Autodesk Fusion 360 part; units mm, degrees
(part 2 of 4)
  line L951 (102.344, 60.9328) -> (103.145, 60.9328)
  line L952 (103.145, 60.9328) -> (103.145, 64.0334)
  line L953 (103.145, 64.0334) -> (102.344, 64.0334)
  line L954 (102.344, 64.0334) -> (102.344, 69.8334)
  line L955 (102.344, 69.8334) -> (103.145, 69.8334)
  line L956 (103.145, 69.8334) -> (103.145, 72.9326)
  line L957 (103.145, 72.9326) -> (102.344, 72.9326)
  line L958 (102.344, 72.9326) -> (102.344, 73.9331)
  line L959 (102.344, 73.9331) -> (88.3447, 73.9331)
  line L960 (107.395, 73.9331) -> (107.395, 72.9326)
  line L961 (107.395, 72.9326) -> (106.594, 72.9326)
  line L962 (106.594, 72.9326) -> (106.594, 69.8334)
  line L963 (106.594, 69.8334) -> (107.395, 69.8334)
  line L964 (107.395, 69.8334) -> (107.395, 64.0334)
  line L965 (107.395, 64.0334) -> (106.594, 64.0334)
  line L966 (106.594, 64.0334) -> (106.594, 60.9328)
  line L967 (106.594, 60.9328) -> (107.395, 60.9328)
  line L968 (107.395, 60.9328) -> (107.395, 59.9338)
  line L969 (107.395, 59.9338) -> (121.394, 59.9338)
  line L970 (121.394, 59.9338) -> (121.394, 60.9328)
  line L971 (121.394, 60.9328) -> (122.195, 60.9328)
  line L972 (122.195, 60.9328) -> (122.195, 64.0334)
  line L973 (122.195, 64.0334) -> (121.394, 64.0334)
  line L974 (121.394, 64.0334) -> (121.394, 69.8334)
  line L975 (121.394, 69.8334) -> (122.195, 69.8334)
  line L976 (122.195, 69.8334) -> (122.195, 72.9326)
  line L977 (122.195, 72.9326) -> (121.394, 72.9326)
  line L978 (121.394, 72.9326) -> (121.394, 73.9331)
  line L979 (121.394, 73.9331) -> (107.395, 73.9331)
  line L980 (126.445, 73.9331) -> (126.445, 72.9326)
  line L981 (126.445, 72.9326) -> (125.644, 72.9326)
  line L982 (125.644, 72.9326) -> (125.644, 69.8334)
  line L983 (125.644, 69.8334) -> (126.445, 69.8334)
  line L984 (126.445, 69.8334) -> (126.445, 64.0334)
  line L985 (126.445, 64.0334) -> (125.644, 64.0334)
  line L986 (125.644, 64.0334) -> (125.644, 60.9328)
  line L987 (125.644, 60.9328) -> (126.445, 60.9328)
  line L988 (126.445, 60.9328) -> (126.445, 59.9338)
  line L989 (126.445, 59.9338) -> (140.444, 59.9338)
  line L990 (140.444, 59.9338) -> (140.444, 60.9328)
  line L991 (140.444, 60.9328) -> (141.245, 60.9328)
  line L992 (141.245, 60.9328) -> (141.245, 64.0334)
  line L993 (141.245, 64.0334) -> (140.444, 64.0334)
  line L994 (140.444, 64.0334) -> (140.444, 69.8334)
  line L995 (140.444, 69.8334) -> (141.245, 69.8334)
  line L996 (141.245, 69.8334) -> (141.245, 72.9326)
  line L997 (141.245, 72.9326) -> (140.444, 72.9326)
  line L998 (140.444, 72.9326) -> (140.444, 73.9331)
  line L999 (140.444, 73.9331) -> (126.445, 73.9331)
  line L1000 (145.495, 73.9331) -> (145.495, 72.9326)
  line L1001 (145.495, 72.9326) -> (144.694, 72.9326)
  line L1002 (144.694, 72.9326) -> (144.694, 69.8334)
  line L1003 (144.694, 69.8334) -> (145.495, 69.8334)
  line L1004 (145.495, 69.8334) -> (145.495, 64.0334)
  line L1005 (145.495, 64.0334) -> (144.694, 64.0334)
  line L1006 (144.694, 64.0334) -> (144.694, 60.9328)
  line L1007 (144.694, 60.9328) -> (145.495, 60.9328)
  line L1008 (145.495, 60.9328) -> (145.495, 59.9338)
  line L1009 (145.495, 59.9338) -> (159.494, 59.9338)
  line L1010 (159.494, 59.9338) -> (159.494, 60.9328)
  line L1011 (159.494, 60.9328) -> (160.295, 60.9328)
  line L1012 (160.295, 60.9328) -> (160.295, 64.0334)
  line L1013 (160.295, 64.0334) -> (159.494, 64.0334)
  line L1014 (159.494, 64.0334) -> (159.494, 69.8334)
  line L1015 (159.494, 69.8334) -> (160.295, 69.8334)
  line L1016 (160.295, 69.8334) -> (160.295, 72.9326)
  line L1017 (160.295, 72.9326) -> (159.494, 72.9326)
  line L1018 (159.494, 72.9326) -> (159.494, 73.9331)
  line L1019 (159.494, 73.9331) -> (145.495, 73.9331)
  line L1020 (164.545, 73.9331) -> (164.545, 72.9326)
  line L1021 (164.545, 72.9326) -> (163.744, 72.9326)
  line L1022 (163.744, 72.9326) -> (163.744, 69.8334)
  line L1023 (163.744, 69.8334) -> (164.545, 69.8334)
  line L1024 (164.545, 69.8334) -> (164.545, 64.0334)
  line L1025 (164.545, 64.0334) -> (163.744, 64.0334)
  line L1026 (163.744, 64.0334) -> (163.744, 60.9328)
  line L1027 (163.744, 60.9328) -> (164.545, 60.9328)
  line L1028 (164.545, 60.9328) -> (164.545, 59.9338)
  line L1029 (164.545, 59.9338) -> (178.544, 59.9338)
  line L1030 (178.544, 59.9338) -> (178.544, 60.9328)
  line L1031 (178.544, 60.9328) -> (179.345, 60.9328)
  line L1032 (179.345, 60.9328) -> (179.345, 64.0334)
  line L1033 (179.345, 64.0334) -> (178.544, 64.0334)
  line L1034 (178.544, 64.0334) -> (178.544, 69.8334)
  line L1035 (178.544, 69.8334) -> (179.345, 69.8334)
  line L1036 (179.345, 69.8334) -> (179.345, 72.9326)
  line L1037 (179.345, 72.9326) -> (178.544, 72.9326)
  line L1038 (178.544, 72.9326) -> (178.544, 73.9331)
  line L1039 (178.544, 73.9331) -> (164.545, 73.9331)
  line L1040 (183.595, 73.9331) -> (183.595, 72.9326)
  line L1041 (183.595, 72.9326) -> (182.794, 72.9326)
  line L1042 (182.794, 72.9326) -> (182.794, 69.8334)
  line L1043 (182.794, 69.8334) -> (183.595, 69.8334)
  line L1044 (183.595, 69.8334) -> (183.595, 64.0334)
  line L1045 (183.595, 64.0334) -> (182.794, 64.0334)
  line L1046 (182.794, 64.0334) -> (182.794, 60.9328)
  line L1047 (182.794, 60.9328) -> (183.595, 60.9328)
  line L1048 (183.595, 60.9328) -> (183.595, 59.9338)
  line L1049 (183.595, 59.9338) -> (197.594, 59.9338)
  line L1050 (197.594, 59.9338) -> (197.594, 60.9328)
  line L1051 (197.594, 60.9328) -> (198.395, 60.9328)
  line L1052 (198.395, 60.9328) -> (198.395, 64.0334)
  line L1053 (198.395, 64.0334) -> (197.594, 64.0334)
  line L1054 (197.594, 64.0334) -> (197.594, 69.8334)
  line L1055 (197.594, 69.8334) -> (198.395, 69.8334)
  line L1056 (198.395, 69.8334) -> (198.395, 72.9326)
  line L1057 (198.395, 72.9326) -> (197.594, 72.9326)
  line L1058 (197.594, 72.9326) -> (197.594, 73.9331)
  line L1059 (197.594, 73.9331) -> (183.595, 73.9331)
  line L1060 (202.645, 73.9331) -> (202.645, 72.9326)
  line L1061 (202.645, 72.9326) -> (201.844, 72.9326)
  line L1062 (201.844, 72.9326) -> (201.844, 69.8334)
  line L1063 (201.844, 69.8334) -> (202.645, 69.8334)
  line L1064 (202.645, 69.8334) -> (202.645, 64.0334)
  line L1065 (202.645, 64.0334) -> (201.844, 64.0334)
  line L1066 (201.844, 64.0334) -> (201.844, 60.9328)
  line L1067 (201.844, 60.9328) -> (202.645, 60.9328)
  line L1068 (202.645, 60.9328) -> (202.645, 59.9338)
  line L1069 (202.645, 59.9338) -> (216.644, 59.9338)
  line L1070 (216.644, 59.9338) -> (216.644, 60.9328)
  line L1071 (216.644, 60.9328) -> (217.445, 60.9328)
  line L1072 (217.445, 60.9328) -> (217.445, 64.0334)
  line L1073 (217.445, 64.0334) -> (216.644, 64.0334)
  line L1074 (216.644, 64.0334) -> (216.644, 69.8334)
  line L1075 (216.644, 69.8334) -> (217.445, 69.8334)
  line L1076 (217.445, 69.8334) -> (217.445, 72.9326)
  line L1077 (217.445, 72.9326) -> (216.644, 72.9326)
  line L1078 (216.644, 72.9326) -> (216.644, 73.9331)
  line L1079 (216.644, 73.9331) -> (202.645, 73.9331)
  line L1080 (221.695, 73.9331) -> (221.695, 72.9326)
  line L1081 (221.695, 72.9326) -> (220.894, 72.9326)
  line L1082 (220.894, 72.9326) -> (220.894, 69.8334)
  line L1083 (220.894, 69.8334) -> (221.695, 69.8334)
  line L1084 (221.695, 69.8334) -> (221.695, 64.0334)
  line L1085 (221.695, 64.0334) -> (220.894, 64.0334)
  line L1086 (220.894, 64.0334) -> (220.894, 60.9328)
  line L1087 (220.894, 60.9328) -> (221.695, 60.9328)
  line L1088 (221.695, 60.9328) -> (221.695, 59.9338)
  line L1089 (221.695, 59.9338) -> (235.694, 59.9338)
  line L1090 (235.694, 59.9338) -> (235.694, 60.9328)
  line L1091 (235.694, 60.9328) -> (236.495, 60.9328)
  line L1092 (236.495, 60.9328) -> (236.495, 64.0334)
  line L1093 (236.495, 64.0334) -> (235.694, 64.0334)
  line L1094 (235.694, 64.0334) -> (235.694, 69.8334)
  line L1095 (235.694, 69.8334) -> (236.495, 69.8334)
  line L1096 (236.495, 69.8334) -> (236.495, 72.9326)
  line L1097 (236.495, 72.9326) -> (235.694, 72.9326)
  line L1098 (235.694, 72.9326) -> (235.694, 73.9331)
  line L1099 (235.694, 73.9331) -> (221.695, 73.9331)
  line L1100 (240.745, 73.9331) -> (240.745, 72.9326)
  line L1101 (240.745, 72.9326) -> (239.944, 72.9326)
  line L1102 (239.944, 72.9326) -> (239.944, 69.8334)
  line L1103 (239.944, 69.8334) -> (240.745, 69.8334)
  line L1104 (240.745, 69.8334) -> (240.745, 64.0334)
  line L1105 (240.745, 64.0334) -> (239.944, 64.0334)
  line L1106 (239.944, 64.0334) -> (239.944, 60.9328)
  line L1107 (239.944, 60.9328) -> (240.745, 60.9328)
  line L1108 (240.745, 60.9328) -> (240.745, 59.9338)
  line L1109 (240.745, 59.9338) -> (254.744, 59.9338)
  line L1110 (254.744, 59.9338) -> (254.744, 60.9328)
  line L1111 (254.744, 60.9328) -> (255.545, 60.9328)
  line L1112 (255.545, 60.9328) -> (255.545, 64.0334)
  line L1113 (255.545, 64.0334) -> (254.744, 64.0334)
  line L1114 (254.744, 64.0334) -> (254.744, 69.8334)
  line L1115 (254.744, 69.8334) -> (255.545, 69.8334)
  line L1116 (255.545, 69.8334) -> (255.545, 72.9326)
  line L1117 (255.545, 72.9326) -> (254.744, 72.9326)
  line L1118 (254.744, 72.9326) -> (254.744, 73.9331)
  line L1119 (254.744, 73.9331) -> (240.745, 73.9331)
  line L1120 (264.557, 73.9331) -> (264.557, 72.9326)
  line L1121 (264.557, 72.9326) -> (263.756, 72.9326)
  line L1122 (263.756, 72.9326) -> (263.756, 69.8334)
  line L1123 (263.756, 69.8334) -> (264.557, 69.8334)
  line L1124 (264.557, 69.8334) -> (264.557, 64.0334)
  line L1125 (264.557, 64.0334) -> (263.756, 64.0334)
  line L1126 (263.756, 64.0334) -> (263.756, 60.9328)
  line L1127 (263.756, 60.9328) -> (264.557, 60.9328)
  line L1128 (264.557, 60.9328) -> (264.557, 59.9338)
  line L1129 (264.557, 59.9338) -> (278.557, 59.9338)
  line L1130 (278.557, 59.9338) -> (278.557, 60.9328)
  line L1131 (278.557, 60.9328) -> (279.356, 60.9328)
  line L1132 (279.356, 60.9328) -> (279.356, 64.0334)
  line L1133 (279.356, 64.0334) -> (278.557, 64.0334)
  line L1134 (278.557, 64.0334) -> (278.557, 69.8334)
  line L1135 (278.557, 69.8334) -> (279.356, 69.8334)
  line L1136 (279.356, 69.8334) -> (279.356, 72.9326)
  line L1137 (279.356, 72.9326) -> (278.557, 72.9326)
  line L1138 (278.557, 72.9326) -> (278.557, 73.9331)
  line L1139 (278.557, 73.9331) -> (264.557, 73.9331)
  line L1140 (288.37, 73.9331) -> (288.37, 72.9326)
  line L1141 (288.37, 72.9326) -> (287.569, 72.9326)
  line L1142 (287.569, 72.9326) -> (287.569, 69.8334)
  line L1143 (287.569, 69.8334) -> (288.37, 69.8334)
  line L1144 (288.37, 69.8334) -> (288.37, 64.0334)
  line L1145 (288.37, 64.0334) -> (287.569, 64.0334)
  line L1146 (287.569, 64.0334) -> (287.569, 60.9328)
  line L1147 (287.569, 60.9328) -> (288.37, 60.9328)
  line L1148 (288.37, 60.9328) -> (288.37, 59.9338)
  line L1149 (288.37, 59.9338) -> (302.369, 59.9338)
  line L1150 (302.369, 59.9338) -> (302.369, 60.9328)
  line L1151 (302.369, 60.9328) -> (303.17, 60.9328)
  line L1152 (303.17, 60.9328) -> (303.17, 64.0334)
  line L1153 (303.17, 64.0334) -> (302.369, 64.0334)
  line L1154 (302.369, 64.0334) -> (302.369, 69.8334)
  line L1155 (302.369, 69.8334) -> (303.17, 69.8334)
  line L1156 (303.17, 69.8334) -> (303.17, 72.9326)
  line L1157 (303.17, 72.9326) -> (302.369, 72.9326)
  line L1158 (302.369, 72.9326) -> (302.369, 73.9331)
  line L1159 (302.369, 73.9331) -> (288.37, 73.9331)
  line L1160 (259.795, 92.9831) -> (259.795, 91.9826)
  line L1161 (259.795, 91.9826) -> (258.994, 91.9826)
  line L1162 (258.994, 91.9826) -> (258.994, 88.8834)
  line L1163 (258.994, 88.8834) -> (259.795, 88.8834)
  line L1164 (259.795, 88.8834) -> (259.795, 88.2826)
  line L1165 (259.795, 88.2826) -> (258.269, 88.2826)
  line L1166 (258.269, 88.2826) -> (258.269, 91.5127)
  line L1167 (258.269, 91.5127) -> (251.52, 91.5127)
  line L1168 (251.52, 91.5127) -> (251.52, 88.2826)
  line L1169 (251.52, 88.2826) -> (250.694, 88.2826)
  line L1170 (250.694, 88.2826) -> (250.694, 85.4837)
  line L1171 (250.694, 85.4837) -> (251.52, 85.4837)
  line L1172 (251.52, 85.4837) -> (251.52, 79.2138)
  line L1173 (251.52, 79.2138) -> (253.243, 79.2138)
  line L1174 (253.243, 79.2138) -> (253.243, 78.0136)
  line L1175 (253.243, 78.0136) -> (256.544, 78.0136)
  line L1176 (256.544, 78.0136) -> (256.544, 79.2138)
  line L1177 (256.544, 79.2138) -> (258.269, 79.2138)
  line L1178 (258.269, 79.2138) -> (258.269, 83.6828)
  line L1179 (258.269, 83.6828) -> (259.795, 83.6828)
  line L1180 (259.795, 83.6828) -> (259.795, 83.0834)
  line L1181 (259.795, 83.0834) -> (258.994, 83.0834)
  line L1182 (258.994, 83.0834) -> (258.994, 79.9828)
  line L1183 (258.994, 79.9828) -> (259.795, 79.9828)
  line L1184 (259.795, 79.9828) -> (259.795, 78.9838)
  line L1185 (259.795, 78.9838) -> (273.794, 78.9838)
  line L1186 (273.794, 78.9838) -> (273.794, 79.9828)
  line L1187 (273.794, 79.9828) -> (274.595, 79.9828)
  line L1188 (274.595, 79.9828) -> (274.595, 83.0834)
  line L1189 (274.595, 83.0834) -> (273.794, 83.0834)
  line L1190 (273.794, 83.0834) -> (273.794, 83.6828)
  line L1191 (273.794, 83.6828) -> (275.32, 83.6828)
  line L1192 (275.32, 83.6828) -> (275.32, 79.2138)
  line L1193 (275.32, 79.2138) -> (277.045, 79.2138)
  line L1194 (277.045, 79.2138) -> (277.045, 78.0136)
  line L1195 (277.045, 78.0136) -> (280.344, 78.0136)
  line L1196 (280.344, 78.0136) -> (280.344, 79.2138)
  line L1197 (280.344, 79.2138) -> (282.069, 79.2138)
  line L1198 (282.069, 79.2138) -> (282.069, 85.4837)
  line L1199 (282.069, 85.4837) -> (282.895, 85.4837)
  line L1200 (282.895, 85.4837) -> (282.895, 88.2826)
  line L1201 (282.895, 88.2826) -> (282.069, 88.2826)
  line L1202 (282.069, 88.2826) -> (282.069, 91.5127)
  line L1203 (282.069, 91.5127) -> (275.32, 91.5127)
  line L1204 (275.32, 91.5127) -> (275.32, 88.2826)
  line L1205 (275.32, 88.2826) -> (273.794, 88.2826)
  line L1206 (273.794, 88.2826) -> (273.794, 88.8834)
  line L1207 (273.794, 88.8834) -> (274.595, 88.8834)
  line L1208 (274.595, 88.8834) -> (274.595, 91.9826)
  line L1209 (274.595, 91.9826) -> (273.794, 91.9826)
  line L1210 (273.794, 91.9826) -> (273.794, 92.9831)
  line L1211 (273.794, 92.9831) -> (259.795, 92.9831)
  line L1212 (2.6197, 92.9831) -> (2.6197, 91.9826)
  line L1213 (2.6197, 91.9826) -> (1.819, 91.9826)
  line L1214 (1.819, 91.9826) -> (1.819, 88.8834)
  line L1215 (1.819, 88.8834) -> (2.6197, 88.8834)
  line L1216 (2.6197, 88.8834) -> (2.6197, 83.0834)
  line L1217 (2.6197, 83.0834) -> (1.819, 83.0834)
  line L1218 (1.819, 83.0834) -> (1.819, 79.9828)
  line L1219 (1.819, 79.9828) -> (2.6197, 79.9828)
  line L1220 (2.6197, 79.9828) -> (2.6197, 78.9838)
  line L1221 (2.6197, 78.9838) -> (16.6192, 78.9838)
  line L1222 (16.6192, 78.9838) -> (16.6192, 79.9828)
  line L1223 (16.6192, 79.9828) -> (17.4198, 79.9828)
  line L1224 (17.4198, 79.9828) -> (17.4198, 83.0834)
  line L1225 (17.4198, 83.0834) -> (16.6192, 83.0834)
  line L1226 (16.6192, 83.0834) -> (16.6192, 88.8834)
  line L1227 (16.6192, 88.8834) -> (17.4198, 88.8834)
  line L1228 (17.4198, 88.8834) -> (17.4198, 91.9826)
  line L1229 (17.4198, 91.9826) -> (16.6192, 91.9826)
  line L1230 (16.6192, 91.9826) -> (16.6192, 92.9831)
  line L1231 (16.6192, 92.9831) -> (2.6196, 92.9831)
  line L1232 (21.6697, 92.9831) -> (21.6697, 91.9826)
  line L1233 (21.6697, 91.9826) -> (20.869, 91.9826)
  line L1234 (20.869, 91.9826) -> (20.869, 88.8834)
  line L1235 (20.869, 88.8834) -> (21.6697, 88.8834)
  line L1236 (21.6697, 88.8834) -> (21.6697, 83.0834)
  line L1237 (21.6697, 83.0834) -> (20.869, 83.0834)
  line L1238 (20.869, 83.0834) -> (20.869, 79.9828)
  line L1239 (20.869, 79.9828) -> (21.6697, 79.9828)
  line L1240 (21.6697, 79.9828) -> (21.6697, 78.9838)
  line L1241 (21.6697, 78.9838) -> (35.669, 78.9838)
  line L1242 (35.669, 78.9838) -> (35.669, 79.9828)
  line L1243 (35.669, 79.9828) -> (36.4698, 79.9828)
  line L1244 (36.4698, 79.9828) -> (36.4698, 83.0834)
  line L1245 (36.4698, 83.0834) -> (35.669, 83.0834)
  line L1246 (35.669, 83.0834) -> (35.669, 88.8834)
  line L1247 (35.669, 88.8834) -> (36.4698, 88.8834)
  line L1248 (36.4698, 88.8834) -> (36.4698, 91.9826)
  line L1249 (36.4698, 91.9826) -> (35.669, 91.9826)
  line L1250 (35.669, 91.9826) -> (35.669, 92.9831)
  line L1251 (35.669, 92.9831) -> (21.6697, 92.9831)
  line L1252 (40.7197, 92.9831) -> (40.7197, 91.9826)
  line L1253 (40.7197, 91.9826) -> (39.9189, 91.9826)
  line L1254 (39.9189, 91.9826) -> (39.9189, 88.8834)
  line L1255 (39.9189, 88.8834) -> (40.7197, 88.8834)
  line L1256 (40.7197, 88.8834) -> (40.7197, 83.0834)
  line L1257 (40.7197, 83.0834) -> (39.9189, 83.0834)
  line L1258 (39.9189, 83.0834) -> (39.9189, 79.9828)
  line L1259 (39.9189, 79.9828) -> (40.7197, 79.9828)
  line L1260 (40.7197, 79.9828) -> (40.7197, 78.9838)
  line L1261 (40.7197, 78.9838) -> (54.719, 78.9838)
  line L1262 (54.719, 78.9838) -> (54.719, 79.9828)
  line L1263 (54.719, 79.9828) -> (55.5198, 79.9828)
  line L1264 (55.5198, 79.9828) -> (55.5198, 83.0834)
  line L1265 (55.5198, 83.0834) -> (54.719, 83.0834)
  line L1266 (54.719, 83.0834) -> (54.719, 88.8834)
  line L1267 (54.719, 88.8834) -> (55.5198, 88.8834)
  line L1268 (55.5198, 88.8834) -> (55.5198, 91.9826)
  line L1269 (55.5198, 91.9826) -> (54.719, 91.9826)
  line L1270 (54.719, 91.9826) -> (54.719, 92.9831)
  line L1271 (54.719, 92.9831) -> (40.7197, 92.9831)
  line L1272 (59.7697, 92.9831) -> (59.7697, 91.9826)
  line L1273 (59.7697, 91.9826) -> (58.9689, 91.9826)
  line L1274 (58.9689, 91.9826) -> (58.9689, 88.8834)
  line L1275 (58.9689, 88.8834) -> (59.7697, 88.8834)
  line L1276 (59.7697, 88.8834) -> (59.7697, 83.0834)
  line L1277 (59.7697, 83.0834) -> (58.9689, 83.0834)
  line L1278 (58.9689, 83.0834) -> (58.9689, 79.9828)
  line L1279 (58.9689, 79.9828) -> (59.7697, 79.9828)
  line L1280 (59.7697, 79.9828) -> (59.7697, 78.9838)
  line L1281 (59.7697, 78.9838) -> (73.769, 78.9838)
  line L1282 (73.769, 78.9838) -> (73.769, 79.9828)
  line L1283 (73.769, 79.9828) -> (74.5698, 79.9828)
  line L1284 (74.5698, 79.9828) -> (74.5698, 83.0834)
  line L1285 (74.5698, 83.0834) -> (73.769, 83.0834)
  line L1286 (73.769, 83.0834) -> (73.769, 88.8834)
  line L1287 (73.769, 88.8834) -> (74.5698, 88.8834)
  line L1288 (74.5698, 88.8834) -> (74.5698, 91.9826)
  line L1289 (74.5698, 91.9826) -> (73.769, 91.9826)
  line L1290 (73.769, 91.9826) -> (73.769, 92.9831)
  line L1291 (73.769, 92.9831) -> (59.7697, 92.9831)
  line L1292 (78.8197, 92.9831) -> (78.8197, 91.9826)
  line L1293 (78.8197, 91.9826) -> (78.0189, 91.9826)
  line L1294 (78.0189, 91.9826) -> (78.0189, 88.8834)
  line L1295 (78.0189, 88.8834) -> (78.8197, 88.8834)
  line L1296 (78.8197, 88.8834) -> (78.8197, 83.0834)
  line L1297 (78.8197, 83.0834) -> (78.0189, 83.0834)
  line L1298 (78.0189, 83.0834) -> (78.0189, 79.9828)
  line L1299 (78.0189, 79.9828) -> (78.8197, 79.9828)
  line L1300 (78.8197, 79.9828) -> (78.8197, 78.9838)
  line L1301 (78.8197, 78.9838) -> (92.819, 78.9838)
  line L1302 (92.819, 78.9838) -> (92.819, 79.9828)
  line L1303 (92.819, 79.9828) -> (93.6184, 79.9828)
  line L1304 (93.6184, 79.9828) -> (93.6184, 83.0834)
  line L1305 (93.6184, 83.0834) -> (92.819, 83.0834)
  line L1306 (92.819, 83.0834) -> (92.819, 88.8834)
  line L1307 (92.819, 88.8834) -> (93.6184, 88.8834)
  line L1308 (93.6184, 88.8834) -> (93.6184, 91.9826)
  line L1309 (93.6184, 91.9826) -> (92.819, 91.9826)
  line L1310 (92.819, 91.9826) -> (92.819, 92.9831)
  line L1311 (92.819, 92.9831) -> (78.8197, 92.9831)
  line L1312 (97.8683, 92.9831) -> (97.8683, 91.9826)
  line L1313 (97.8683, 91.9826) -> (97.0689, 91.9826)
  line L1314 (97.0689, 91.9826) -> (97.0689, 88.8834)
  line L1315 (97.0689, 88.8834) -> (97.8683, 88.8834)
  line L1316 (97.8683, 88.8834) -> (97.8683, 83.0834)
  line L1317 (97.8683, 83.0834) -> (97.0689, 83.0834)
  line L1318 (97.0689, 83.0834) -> (97.0689, 79.9828)
  line L1319 (97.0689, 79.9828) -> (97.8683, 79.9828)
  line L1320 (97.8683, 79.9828) -> (97.8683, 78.9838)
  line L1321 (97.8683, 78.9838) -> (111.869, 78.9838)
  line L1322 (111.869, 78.9838) -> (111.869, 79.9828)
  line L1323 (111.869, 79.9828) -> (112.668, 79.9828)
  line L1324 (112.668, 79.9828) -> (112.668, 83.0834)
  line L1325 (112.668, 83.0834) -> (111.869, 83.0834)
  line L1326 (111.869, 83.0834) -> (111.869, 88.8834)
  line L1327 (111.869, 88.8834) -> (112.668, 88.8834)
  line L1328 (112.668, 88.8834) -> (112.668, 91.9826)
  line L1329 (112.668, 91.9826) -> (111.869, 91.9826)
  line L1330 (111.869, 91.9826) -> (111.869, 92.9831)
  line L1331 (111.869, 92.9831) -> (97.8683, 92.9831)
  line L1332 (116.918, 92.9831) -> (116.918, 91.9826)
  line L1333 (116.918, 91.9826) -> (116.119, 91.9826)
  line L1334 (116.119, 91.9826) -> (116.119, 88.8834)
  line L1335 (116.119, 88.8834) -> (116.918, 88.8834)
  line L1336 (116.918, 88.8834) -> (116.918, 83.0834)
  line L1337 (116.918, 83.0834) -> (116.119, 83.0834)
  line L1338 (116.119, 83.0834) -> (116.119, 79.9828)
  line L1339 (116.119, 79.9828) -> (116.918, 79.9828)
  line L1340 (116.918, 79.9828) -> (116.918, 78.9838)
  line L1341 (116.918, 78.9838) -> (130.919, 78.9838)
  line L1342 (130.919, 78.9838) -> (130.919, 79.9828)
  line L1343 (130.919, 79.9828) -> (131.72, 79.9828)
  line L1344 (131.72, 79.9828) -> (131.72, 83.0834)
  line L1345 (131.72, 83.0834) -> (130.919, 83.0834)
  line L1346 (130.919, 83.0834) -> (130.919, 88.8834)
  line L1347 (130.919, 88.8834) -> (131.72, 88.8834)
  line L1348 (131.72, 88.8834) -> (131.72, 91.9826)
  line L1349 (131.72, 91.9826) -> (130.919, 91.9826)
  line L1350 (130.919, 91.9826) -> (130.919, 92.9831)
  line L1351 (130.919, 92.9831) -> (116.918, 92.9831)
  line L1352 (135.97, 92.9831) -> (135.97, 91.9826)
  line L1353 (135.97, 91.9826) -> (135.169, 91.9826)
  line L1354 (135.169, 91.9826) -> (135.169, 88.8834)
  line L1355 (135.169, 88.8834) -> (135.97, 88.8834)
  line L1356 (135.97, 88.8834) -> (135.97, 83.0834)
  line L1357 (135.97, 83.0834) -> (135.169, 83.0834)
  line L1358 (135.169, 83.0834) -> (135.169, 79.9828)
  line L1359 (135.169, 79.9828) -> (135.97, 79.9828)
  line L1360 (135.97, 79.9828) -> (135.97, 78.9838)
  line L1361 (135.97, 78.9838) -> (149.969, 78.9838)
  line L1362 (149.969, 78.9838) -> (149.969, 79.9828)
  line L1363 (149.969, 79.9828) -> (150.77, 79.9828)
  line L1364 (150.77, 79.9828) -> (150.77, 83.0834)
  line L1365 (150.77, 83.0834) -> (149.969, 83.0834)
  line L1366 (149.969, 83.0834) -> (149.969, 88.8834)
  line L1367 (149.969, 88.8834) -> (150.77, 88.8834)
  line L1368 (150.77, 88.8834) -> (150.77, 91.9826)
  line L1369 (150.77, 91.9826) -> (149.969, 91.9826)
  line L1370 (149.969, 91.9826) -> (149.969, 92.9831)
  line L1371 (149.969, 92.9831) -> (135.97, 92.9831)
  line L1372 (155.02, 92.9831) -> (155.02, 91.9826)
  line L1373 (155.02, 91.9826) -> (154.219, 91.9826)
  line L1374 (154.219, 91.9826) -> (154.219, 88.8834)
  line L1375 (154.219, 88.8834) -> (155.02, 88.8834)
  line L1376 (155.02, 88.8834) -> (155.02, 83.0834)
  line L1377 (155.02, 83.0834) -> (154.219, 83.0834)
  line L1378 (154.219, 83.0834) -> (154.219, 79.9828)
  line L1379 (154.219, 79.9828) -> (155.02, 79.9828)
  line L1380 (155.02, 79.9828) -> (155.02, 78.9838)
  line L1381 (155.02, 78.9838) -> (169.019, 78.9838)
  line L1382 (169.019, 78.9838) -> (169.019, 79.9828)
  line L1383 (169.019, 79.9828) -> (169.82, 79.9828)
  line L1384 (169.82, 79.9828) -> (169.82, 83.0834)
  line L1385 (169.82, 83.0834) -> (169.019, 83.0834)
  line L1386 (169.019, 83.0834) -> (169.019, 88.8834)
  line L1387 (169.019, 88.8834) -> (169.82, 88.8834)
  line L1388 (169.82, 88.8834) -> (169.82, 91.9826)
  line L1389 (169.82, 91.9826) -> (169.019, 91.9826)
  line L1390 (169.019, 91.9826) -> (169.019, 92.9831)
  line L1391 (169.019, 92.9831) -> (155.02, 92.9831)
  line L1392 (174.07, 92.9831) -> (174.07, 91.9826)
  line L1393 (174.07, 91.9826) -> (173.269, 91.9826)
  line L1394 (173.269, 91.9826) -> (173.269, 88.8834)
  line L1395 (173.269, 88.8834) -> (174.07, 88.8834)
  line L1396 (174.07, 88.8834) -> (174.07, 83.0834)
  line L1397 (174.07, 83.0834) -> (173.269, 83.0834)
  line L1398 (173.269, 83.0834) -> (173.269, 79.9828)
  line L1399 (173.269, 79.9828) -> (174.07, 79.9828)
  line L1400 (174.07, 79.9828) -> (174.07, 78.9838)
  line L1401 (174.07, 78.9838) -> (188.069, 78.9838)
  line L1402 (188.069, 78.9838) -> (188.069, 79.9828)
  line L1403 (188.069, 79.9828) -> (188.87, 79.9828)
  line L1404 (188.87, 79.9828) -> (188.87, 83.0834)
  line L1405 (188.87, 83.0834) -> (188.069, 83.0834)
  line L1406 (188.069, 83.0834) -> (188.069, 88.8834)
  line L1407 (188.069, 88.8834) -> (188.87, 88.8834)
  line L1408 (188.87, 88.8834) -> (188.87, 91.9826)
  line L1409 (188.87, 91.9826) -> (188.069, 91.9826)
  line L1410 (188.069, 91.9826) -> (188.069, 92.9831)
  line L1411 (188.069, 92.9831) -> (174.07, 92.9831)
  line L1412 (193.12, 92.9831) -> (193.12, 91.9826)
  line L1413 (193.12, 91.9826) -> (192.319, 91.9826)
  line L1414 (192.319, 91.9826) -> (192.319, 88.8834)
  line L1415 (192.319, 88.8834) -> (193.12, 88.8834)
  line L1416 (193.12, 88.8834) -> (193.12, 83.0834)
  line L1417 (193.12, 83.0834) -> (192.319, 83.0834)
  line L1418 (192.319, 83.0834) -> (192.319, 79.9828)
  line L1419 (192.319, 79.9828) -> (193.12, 79.9828)
  line L1420 (193.12, 79.9828) -> (193.12, 78.9838)
  line L1421 (193.12, 78.9838) -> (207.119, 78.9838)
  line L1422 (207.119, 78.9838) -> (207.119, 79.9828)
  line L1423 (207.119, 79.9828) -> (207.92, 79.9828)
  line L1424 (207.92, 79.9828) -> (207.92, 83.0834)
  line L1425 (207.92, 83.0834) -> (207.119, 83.0834)
  line L1426 (207.119, 83.0834) -> (207.119, 88.8834)
  line L1427 (207.119, 88.8834) -> (207.92, 88.8834)
  line L1428 (207.92, 88.8834) -> (207.92, 91.9826)
  line L1429 (207.92, 91.9826) -> (207.119, 91.9826)
  line L1430 (207.119, 91.9826) -> (207.119, 92.9831)
  line L1431 (207.119, 92.9831) -> (193.12, 92.9831)
  line L1432 (212.17, 92.9831) -> (212.17, 91.9826)
  line L1433 (212.17, 91.9826) -> (211.369, 91.9826)
  line L1434 (211.369, 91.9826) -> (211.369, 88.8834)
  line L1435 (211.369, 88.8834) -> (212.17, 88.8834)
  line L1436 (212.17, 88.8834) -> (212.17, 83.0834)
  line L1437 (212.17, 83.0834) -> (211.369, 83.0834)
  line L1438 (211.369, 83.0834) -> (211.369, 79.9828)
  line L1439 (211.369, 79.9828) -> (212.17, 79.9828)
  line L1440 (212.17, 79.9828) -> (212.17, 78.9838)
  line L1441 (212.17, 78.9838) -> (226.169, 78.9838)
  line L1442 (226.169, 78.9838) -> (226.169, 79.9828)
  line L1443 (226.169, 79.9828) -> (226.97, 79.9828)
  line L1444 (226.97, 79.9828) -> (226.97, 83.0834)
  line L1445 (226.97, 83.0834) -> (226.169, 83.0834)
  line L1446 (226.169, 83.0834) -> (226.169, 88.8834)
  line L1447 (226.169, 88.8834) -> (226.97, 88.8834)
  line L1448 (226.97, 88.8834) -> (226.97, 91.9826)
  line L1449 (226.97, 91.9826) -> (226.169, 91.9826)
  line L1450 (226.169, 91.9826) -> (226.169, 92.9831)
  line L1451 (226.169, 92.9831) -> (212.17, 92.9831)
  line L1452 (231.22, 92.9831) -> (231.22, 91.9826)
  line L1453 (231.22, 91.9826) -> (230.419, 91.9826)
  line L1454 (230.419, 91.9826) -> (230.419, 88.8834)
  line L1455 (230.419, 88.8834) -> (231.22, 88.8834)
  line L1456 (231.22, 88.8834) -> (231.22, 83.0834)
  line L1457 (231.22, 83.0834) -> (230.419, 83.0834)
  line L1458 (230.419, 83.0834) -> (230.419, 79.9828)
  line L1459 (230.419, 79.9828) -> (231.22, 79.9828)
  line L1460 (231.22, 79.9828) -> (231.22, 78.9838)
  line L1461 (231.22, 78.9838) -> (245.219, 78.9838)
  line L1462 (245.219, 78.9838) -> (245.219, 79.9828)
  line L1463 (245.219, 79.9828) -> (246.02, 79.9828)
  line L1464 (246.02, 79.9828) -> (246.02, 83.0834)
  line L1465 (246.02, 83.0834) -> (245.219, 83.0834)
  line L1466 (245.219, 83.0834) -> (245.219, 88.8834)
  line L1467 (245.219, 88.8834) -> (246.02, 88.8834)
  line L1468 (246.02, 88.8834) -> (246.02, 91.9826)
  line L1469 (246.02, 91.9826) -> (245.219, 91.9826)
  line L1470 (245.219, 91.9826) -> (245.219, 92.9831)
  line L1471 (245.219, 92.9831) -> (231.22, 92.9831)
  line L1472 (288.37, 92.9831) -> (288.37, 91.9826)
  line L1473 (288.37, 91.9826) -> (287.569, 91.9826)
  line L1474 (287.569, 91.9826) -> (287.569, 88.8834)
  line L1475 (287.569, 88.8834) -> (288.37, 88.8834)
  line L1476 (288.37, 88.8834) -> (288.37, 83.0834)
  line L1477 (288.37, 83.0834) -> (287.569, 83.0834)
  line L1478 (287.569, 83.0834) -> (287.569, 79.9828)
  line L1479 (287.569, 79.9828) -> (288.37, 79.9828)
  line L1480 (288.37, 79.9828) -> (288.37, 78.9838)
  line L1481 (288.37, 78.9838) -> (302.369, 78.9838)
  line L1482 (302.369, 78.9838) -> (302.369, 79.9828)
  line L1483 (302.369, 79.9828) -> (303.17, 79.9828)
  line L1484 (303.17, 79.9828) -> (303.17, 83.0834)
  line L1485 (303.17, 83.0834) -> (302.369, 83.0834)
  line L1486 (302.369, 83.0834) -> (302.369, 88.8834)
  line L1487 (302.369, 88.8834) -> (303.17, 88.8834)
  line L1488 (303.17, 88.8834) -> (303.17, 91.9826)
  line L1489 (303.17, 91.9826) -> (302.369, 91.9826)
  line L1490 (302.369, 91.9826) -> (302.369, 92.9831)
  line L1491 (302.369, 92.9831) -> (288.37, 92.9831)
extrude "Extrude1" add sketch "ae37414ef1056c08ddbac5ef96bec674ccce9e3e_switch" along normal blind 1.5 makes body 1
extrude "Extrude2" add 1 faces at (157.0937, 15.5337, 0) along direction (0, 0, -1) blind 3.5 separate body on bodies 1 makes body 2
extrude "Extrude3" cut 15 faces at (297.7027, 92.9831, -1.1667) (269.1277, 92.9831, -1.1667) (240.5527, 92.9831, -1.1667) (221.5027, 92.9831, -1.1667) (202.4527, 92.9831, -1.1667) (183.4027, 92.9831, -1.1667) (164.3527, 92.9831, -1.1667) (69.1026, 92.9831, -1.1667) (145.3027, 92.9831, -1.1667) (126.252, 92.9831, -1.1667) (107.2021, 92.9831, -1.1667) (88.1526, 92.9831, -1.1667) (11.9527, 92.9831, -1.1667) (31.0026, 92.9831, -1.1667) (50.0526, 92.9831, -1.1667) along direction (0, 1, 0) blind 1 on bodies 2 bodies 2
extrude "Extrude4" cut 15 faces at (297.7027, 73.9331, -1.1667) (273.8903, 73.9331, -1.1667) (250.0777, 73.9331, -1.1667) (231.0277, 73.9331, -1.1667) (211.9777, 73.9331, -1.1667) (192.9277, 73.9331, -1.1667) (173.8777, 73.9331, -1.1667) (154.8277, 73.9331, -1.1667) (135.7777, 73.9331, -1.1667) (116.7277, 73.9331, -1.1667) (97.6776, 73.9331, -1.1667) (78.6276, 73.9331, -1.1667) (59.5776, 73.9331, -1.1667) (40.5276, 73.9331, -1.1667) (16.7152, 73.9331, -1.1667) along direction (0, 1, 0) blind 1 on bodies 2 bodies 2
extrude "Extrude5" cut 14 faces at (297.7027, 54.8831, -1.1667) (266.746, 54.8831, -1.1667) (235.7903, 54.8831, -1.1667) (216.7403, 54.8831, -1.1667) (197.6903, 54.8831, -1.1667) (178.6403, 54.8831, -1.1667) (159.5903, 54.8831, -1.1667) (140.5403, 54.8831, -1.1667) (121.4903, 54.8831, -1.1667) (102.4404, 54.8831, -1.1667) (83.3901, 54.8831, -1.1667) (64.3401, 54.8831, -1.1667) (45.2901, 54.8831, -1.1667) (14.429, 54.8831, -2.3333) along direction (0, 1, 0) blind 1 on bodies 2 bodies 2
extrude "Extrude6" cut 14 faces at (297.7027, 35.833, -1.1667) (278.6527, 35.833, -1.1667) (252.4587, 35.833, -1.1667) (226.2653, 35.833, -1.1667) (207.2153, 35.833, -1.1667) (188.1653, 35.833, -1.1667) (169.1153, 35.833, -1.1667) (150.0653, 35.833, -1.1667) (131.0153, 35.833, -1.1667) (111.9653, 35.833, -1.1667) (92.9151, 35.833, -1.1667) (73.8651, 35.833, -1.1667) (54.8151, 35.833, -1.1667) (23.8589, 35.833, -1.1667) along direction (0, 1, 0) blind 1 on bodies 2 bodies 2
extrude "Extrude7" cut 10 faces at (297.7027, 16.7831, -1.1667) (278.6527, 16.7831, -1.1667) (259.6027, 16.7831, -1.1667) (240.5527, 16.7831, -1.1667) (221.5027, 16.7831, -1.1667) (202.4527, 16.7831, -1.1667) (133.396, 16.7831, -1.1667) (61.9589, 16.7831, -1.1667) (38.1459, 16.7831, -2.3333) (14.3339, 16.7831, -1.1667) along direction (0, 1, 0) blind 1 on bodies 2 bodies 2
extrude "Extrude8" cut 10 faces at (9.6674, 2.7836, -1.1667) (33.4789, 2.7836, -2.3333) (57.2924, 2.7836, -1.1667) (128.729, 2.7836, -1.1667) (197.7863, 2.7836, -1.1667) (216.8363, 2.7836, -1.1667) (235.8863, 2.7836, -1.1667) (254.9363, 2.7836, -1.1667) (273.9863, 2.7836, -1.1667) (293.0363, 2.7836, -1.1667) along direction (0, -1, 0) blind 1 on bodies 2 bodies 2
extrude "Extrude9" cut 14 faces at (19.1924, 21.8336, -1.1667) (50.1486, 21.8336, -1.1667) (69.1986, 21.8336, -1.1667) (88.2486, 21.8336, -1.1667) (107.2987, 21.8336, -1.1667) (293.0363, 21.8336, -1.1667) (273.9863, 21.8336, -1.1667) (247.7923, 21.8336, -1.1667) (221.5987, 21.8336, -1.1667) (126.3487, 21.8336, -1.1667) (145.3987, 21.8336, -1.1667) (164.4487, 21.8336, -1.1667) (183.4987, 21.8336, -1.1667) (202.5487, 21.8336, -1.1667) along direction (0, -1, 0) blind 1 on bodies 2 bodies 2
extrude "Extrude10" cut 14 faces at (19.0959, 40.8838, -2.3333) (40.6236, 40.8838, -1.1667) (59.6736, 40.8838, -1.1667) (78.7236, 40.8838, -1.1667) (97.7738, 40.8838, -1.1667) (116.8237, 40.8838, -1.1667) (135.8737, 40.8838, -1.1667) (154.9237, 40.8838, -1.1667) (173.9737, 40.8838, -1.1667) (193.0237, 40.8838, -1.1667) (212.0737, 40.8838, -1.1667) (231.1237, 40.8838, -1.1667) (262.079, 40.8838, -1.1667) (293.0363, 40.8838, -1.1667) along direction (0, -1, 0) blind 1 on bodies 2 bodies 2
extrude "Extrude11" cut 15 faces at (293.0363, 59.9338, -1.1667) (269.2237, 59.9338, -1.1667) (245.4113, 59.9338, -1.1667) (226.3613, 59.9338, -1.1667) (207.3113, 59.9338, -1.1667) (188.2613, 59.9338, -1.1667) (169.2113, 59.9338, -1.1667) (112.0613, 59.9338, -1.1667) (131.1113, 59.9338, -1.1667) (150.1613, 59.9338, -1.1667) (73.9611, 59.9338, -1.1667) (93.0111, 59.9338, -1.1667) (54.9111, 59.9338, -1.1667) (35.8611, 59.9338, -1.1667) (12.0487, 59.9338, -1.1667) along direction (0, -1, 0) blind 1 on bodies 2 bodies 2
extrude "Extrude12" cut 15 faces at (7.2862, 78.9838, -1.1667) (26.3361, 78.9838, -1.1667) (45.3861, 78.9838, -1.1667) (64.4361, 78.9838, -1.1667) (83.4861, 78.9838, -1.1667) (102.5352, 78.9838, -1.1667) (121.585, 78.9838, -1.1667) (140.6363, 78.9838, -1.1667) (159.6863, 78.9838, -1.1667) (178.7363, 78.9838, -1.1667) (197.7863, 78.9838, -1.1667) (216.8363, 78.9838, -1.1667) (235.8863, 78.9838, -1.1667) (264.4613, 78.9838, -1.1667) (293.0363, 78.9838, -1.1667) along direction (0, -1, 0) blind 1 on bodies 2 bodies 2